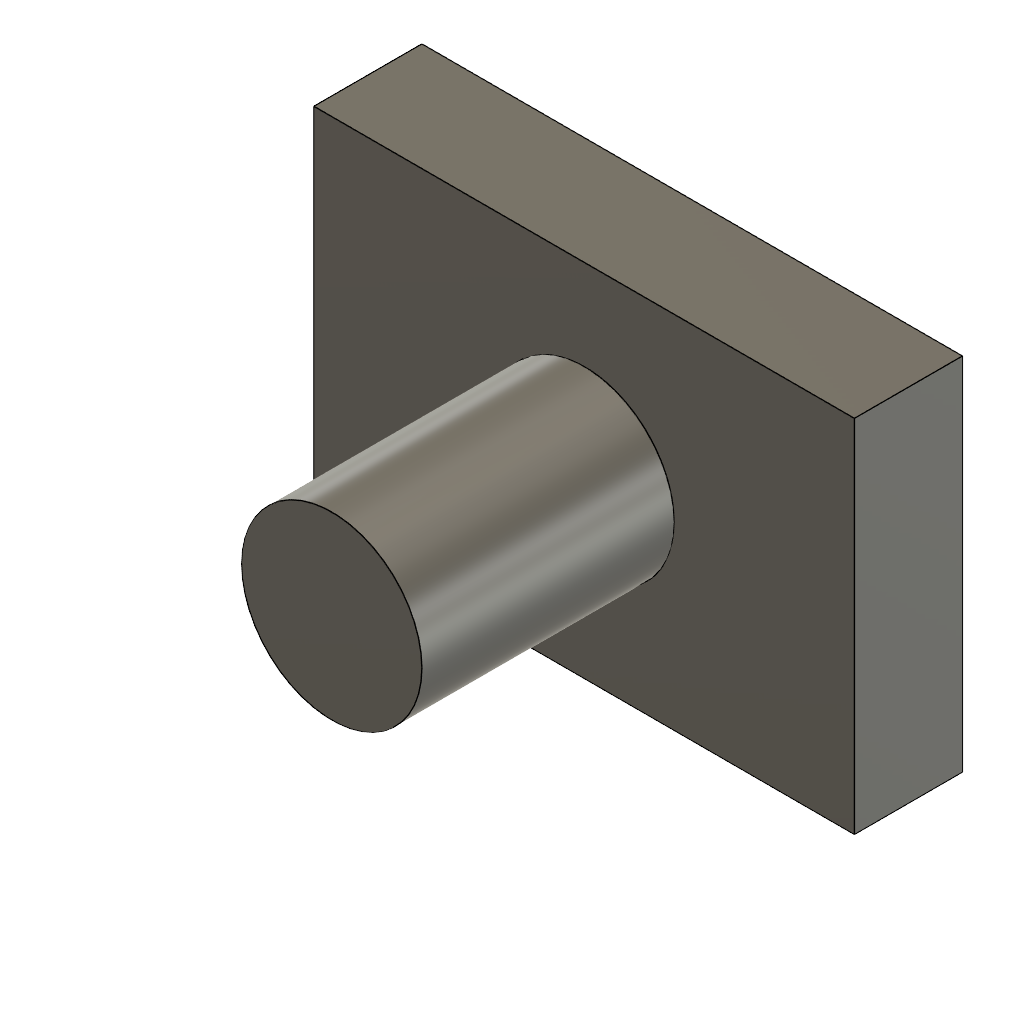
split_body_by_tool_body (Autodesk Fusion 360 design; units mm, degrees)
part number: 2026-11-13-14-47-01-192
Autodesk Fusion 360 part; units mm, degrees
sketch "Sketch1" plane through (0, 0, 0) normal (0, 0, 1) x (1, 0, 0)
  line L0 (0, 0) -> (30, 0)
  line L1 (30, 0) -> (30, 20)
  line L2 (30, 20) -> (0, 20)
  line L3 (0, 20) -> (0, 0)
extrude "Extrude1" add sketch "Sketch1" along normal blind 6 makes body 1
sketch "Sketch2" plane through (0, 0, 0) normal (0, 0, 1) x (1, 0, 0)
  circle A0 centre (15, 10) radius 5
extrude "Extrude2" add sketch "Sketch2" along normal blind 20 separate body makes body 2
split "Split1" by bodies 2 bodies 1 makes body 3 at (3.3333, 10, 0)
